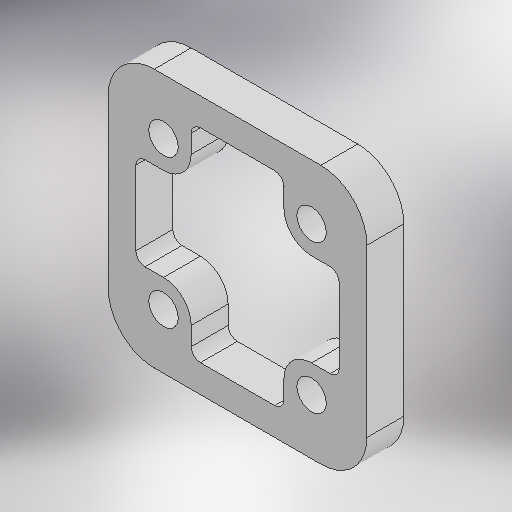
# Autodesk Inventor part: 3D_encoder-mount
Saved by Autodesk Inventor 2025.3 (Build 293356030, 356C)
## iProperties
Created: 2026-09-06
Part Number: 3D_encoder-mount
Material: 一般
Document SubType Name: Modeling
Designer: ibuki_ono
Density: 1 g/cm^3
Appearance: 既定
Author: ibuki_ono
## iProperties of the stored document 3D_encoder-mount_3D プリント.ipt
Created: 2026-09-06
Part Number: 3D_encoder-mount_3D プリント
Material: 一般
Document SubType Name: Modeling
Designer: ibuki_ono
Density: 1 g/cm^3
Appearance: 既定
Author: ibuki_ono
Autodesk Inventor part; units mm, degrees
ref_plane "YZ Plane" through (0, 0, 0) normal (1, 0, 0) x (0, 1, 0)
ref_plane "XZ Plane" through (0, 0, 0) normal (0, 1, 0) x (-1, 0, 0)
ref_plane "XY Plane" through (0, 0, 0) normal (0, 0, 1) x (1, 0, 0)
sketch "スケッチ1" plane through (0, 0, 0) normal (0, 0, 1) x (1, 0, 0)
  line L0 (-8.025, -8.025) -> (8.025, -8.025) construction
  line L1 (8.025, -8.025) -> (8.025, 8.025) construction
  line L2 (8.025, 8.025) -> (-8.025, 8.025) construction
  line L3 (-8.025, 8.025) -> (-8.025, -8.025) construction
  line L4 (-8.025, -8.025) -> (8.025, 8.025) construction
  line L5 (8.025, -8.025) -> (-8.025, 8.025) construction
  circle A0 centre (-8.025, 8.025) radius 3
  circle A1 centre (8.025, 8.025) radius 3
  circle A2 centre (8.025, -8.025) radius 3
  circle A3 centre (-8.025, -8.025) radius 3
  line L6 (11.025, -11.025) -> (-11.025, -11.025)
  line L7 (-11.025, -11.025) -> (-11.025, 11.025)
  line L8 (-11.025, 11.025) -> (11.025, 11.025)
  line L9 (11.025, 11.025) -> (11.025, -11.025)
  line L10 (11.025, -11.025) -> (-11.025, 11.025) construction
  line L11 (-11.025, -11.025) -> (11.025, 11.025) construction
  line L12 (14.025, 14.025) -> (-14.025, 14.025)
  line L13 (-14.025, 14.025) -> (-14.025, -14.025)
  line L14 (-14.025, -14.025) -> (14.025, -14.025)
  line L15 (14.025, -14.025) -> (14.025, 14.025)
  line L16 (-11.025, -5.025) -> (11.025, -5.025)
  line L17 (11.025, -5.025) -> (11.025, 5.025)
  line L18 (11.025, 5.025) -> (-11.025, 5.025)
  line L19 (-11.025, 5.025) -> (-11.025, -5.025)
  line L20 (-11.025, -5.025) -> (11.025, 5.025) construction
  line L21 (11.025, -5.025) -> (-11.025, 5.025) construction
  line L22 (5.025, -11.025) -> (-5.025, -11.025)
  line L23 (-5.025, -11.025) -> (-5.025, 11.025)
  line L24 (-5.025, 11.025) -> (5.025, 11.025)
  line L25 (5.025, 11.025) -> (5.025, -11.025)
  line L26 (5.025, -11.025) -> (-5.025, 11.025) construction
  line L27 (-5.025, -11.025) -> (5.025, 11.025) construction
  point P0 (0, 0)
  point P1 (8.025, -5.025)
  point P2 (5.025, -8.025)
  point P3 (-5.025, -11.025)
  point P4 (-5.025, -8.025)
  point P5 (-8.025, -5.025)
  point P6 (-8.025, 5.025)
  point P7 (-5.025, 8.025)
  point P8 (5.025, 8.025)
  point P9 (8.025, 5.025)
  dimension "d0" = 16.05
  dimension "d1" = 16.05
  dimension "d2" = 6
  dimension "d3" = 6
  dimension "d4" = 6
  dimension "d5" = 6
  dimension "d6" = 3
  constraints: 56 end point, 10 parallel, 8 midpoint, 5 perpendicular, 4 centre point, 4 coincident, 4 horizontal, 3 point on line, 3 tangent, 3 other
  measures "d0" distance of L2.end L1.end
  measures "d1" distance of L1.end L0.end
  measures "d2" diameter of A0
  measures "d3" diameter of A1
  measures "d4" diameter of A2
  measures "d5" diameter of A3
  measures "d6" distance between parallel lines of L8 L12
extrude "押し出し1" add sketch "スケッチ1" along normal blind 4 contours A0 | A0 L8 L23 | A0 L7 L8 | L18 L7 A0 | L8 A1 L25 | L16 A3 L7 | L8 L9 A1 | A1 | A1 L9 L18 | A3 | L23 L6 A3 | A3 L6 L7 | L16 L9 A2 | A2 | A2 L6 L25 | L9 L6 A2 | L15 L14 L13 L12
sketch "スケッチ2" plane through (0, 0, 4) normal (0, 0, 1) x (1, 0, 0)
  arc A0 (-8.025, 5.025) -> (-5.025, 8.025) centre (-8.025, 8.025) ccw projected
  arc A1 (-5.025, -8.025) -> (-8.025, -5.025) centre (-8.025, -8.025) ccw projected
  arc A2 (8.025, -5.025) -> (5.025, -8.025) centre (8.025, -8.025) ccw projected
  arc A3 (5.025, 8.025) -> (8.025, 5.025) centre (8.025, 8.025) ccw projected
  point P0 (0, 0)
hole "穴1" at (-8.025, 8.025, 4) at (8.025, 8.025, 4) at (8.025, -8.025, 4) at (-8.025, -8.025, 4) direction (0, 0, -1) diameter 3.2 end through all
fillet "フィレット1" radius 5 4 edges at (-14.025, 14.025, 2) (14.025, 14.025, 2) (14.025, -14.025, 2) (-14.025, -14.025, 2)
fillet "フィレット2" radius 1 8 edges at (-11.025, 5.025, 2) (-5.025, 11.025, 2) (5.025, 11.025, 2) (11.025, 5.025, 2) (11.025, -5.025, 2) (5.025, -11.025, 2) (-5.025, -11.025, 2) (-11.025, -5.025, 2)
